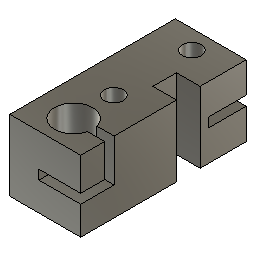
Récupération accélérateur d'origine (Autodesk Fusion 360 archive; units mm, degrees)
design "coulisseau"
Autodesk Fusion 360 part; units mm, degrees
sketch "Esquisse1" plane through (0, 0, 0) normal (0, 0, 1) x (1, 0, 0)
  line L0 (-7.5, 17.5) -> (7.5, 17.5)
  line L1 (7.5, 17.5) -> (7.5, -17.5)
  line L2 (7.5, -17.5) -> (-7.5, -17.5)
  line L3 (-7.5, -17.5) -> (-7.5, 17.5)
  line L4 (0, 50) -> (0, -48.677) construction
  line L5 (-71.4286, 0) -> (60.7143, 0) construction
  circle A0 centre (0, -11.5) radius 4
  circle A1 centre (0, 13.5) radius 2
  circle A2 centre (0, -3) radius 2
  dimension "d1" = 35
  dimension "d2" = 15
  dimension "d3" = 8
  dimension "d4" = 6
  dimension "d7" = 4
  dimension "d8" = 4
  dimension "d15" = 4
  dimension "d16" = 3
  constraint horizontal L0
  constraint vertical L1
  constraint horizontal L2
  constraint vertical L3
  constraint vertical L4
  constraint perpendicular L1 L5
  constraint symmetric L1 L3 L4
  constraint symmetric L0 L2 L5
  constraint coincident L4 A0.centre
  constraint coincident L4 A1.centre
  constraint coincident L4 A2.centre
  measures "d1" distance of L0.end L1.end
  measures "d2" distance of L1.end L2.end
  measures "d3" diameter of A0
  measures "d4" distance of L2 A0.centre
  measures "d7" diameter of A1
  measures "d8" distance of L0 A1.centre
  measures "d15" diameter of A2
  measures "d16" distance of L5 A2.centre
extrude "Extrusion1" add sketch "Esquisse1" along normal blind 15
sketch "Esquisse2" plane through (7.5, 0, 0) normal (1, 0, 0) x (0, 1, 0)
  line L0 (-17.5, 0) -> (17.5, 0)
  line L1 (17.5, 0) -> (17.5, 15)
  line L2 (17.5, 15) -> (-17.5, 15)
  line L3 (-17.5, 15) -> (-17.5, 0)
  line L4 (17.5, 8.5) -> (9.5, 8.5)
  line L5 (9.5, 8.5) -> (9.5, 6.5)
  line L6 (9.5, 6.5) -> (17.5, 6.5)
  line L7 (17.5, 6.5) -> (17.5, 8.5)
  line L8 (-5, 15) -> (-1, 15) construction
  line L9 (-1, 0) -> (-5, 0) construction
  line L10 (11.5, 15) -> (15.5, 15) construction
  line L11 (15.5, 0) -> (11.5, 0) construction
  line L12 (11.5, 15) -> (15.5, 0) construction
  line L13 (-1, 15) -> (-5, 0) construction
  line L14 (13.5, 7.5) -> (-3, 7.5) construction
  line L15 (2.75, 15) -> (7.75, 15)
  line L16 (7.75, 15) -> (7.75, 0)
  line L17 (7.75, 0) -> (2.75, 0)
  line L18 (2.75, 0) -> (2.75, 15)
  line L19 (2.75, 15) -> (7.75, 0) construction
  line L20 (-7.5, 0) -> (-15.5, 0)
  line L21 (-15.5, 15) -> (-7.5, 15)
  line L22 (-7.5, 15) -> (-7.5, 0) construction
  line L23 (-12.4365, 15) -> (-10.4365, 15)
  line L24 (-10.4365, 15) -> (-10.4365, 6.0364)
  line L25 (-10.4365, 6.0364) -> (-12.4365, 6.0364)
  line L26 (-12.4365, 6.0364) -> (-12.4365, 15)
  line L27 (-11.4365, 6.0364) -> (-11.4365, 8) construction
  point P0 (17.5, 7.5)
  point P1 (5.25, 7.5)
  dimension "d10" = 2
  dimension "d11" = 8
  dimension "d17" = 5
  dimension "d20" = 2
  constraint horizontal L4
  constraint vertical L5
  constraint horizontal L6
  constraint vertical L7
  constraint coincident L1 L4.start
  constraint midpoint L7 P0
  constraint coincident L10.start L12.start
  constraint coincident L11.start L12.end
  constraint coincident L8.end L13.start
  constraint coincident L9.end L13.end
  constraint midpoint L13 L14.end
  constraint midpoint L12 L14.start
  constraint midpoint L14 P1
  constraint horizontal L15
  constraint vertical L16
  constraint horizontal L17
  constraint vertical L18
  constraint coincident L0 L16.end
  constraint coincident L2 L15.start
  constraint coincident P1 L19
  constraint coincident L21.end L22.start
  constraint coincident L20.start L22.end
  constraint horizontal L23
  constraint vertical L24
  constraint horizontal L25
  constraint vertical L26
  constraint coincident L21 L23.start
  constraint midpoint L25 L27.start
  constraint perpendicular L25 L27
  measures "d10" distance of L4.start L6.end
  measures "d11" distance of L4.start L4.end
  measures "d17" distance of L15.start L15.end
  measures "d20" distance of L23.start L23.end
extrude "Extrusion2" cut sketch "Esquisse2" against normal up to surface (15 mm away) contours L1 L4 L5 L6 L7
extrude "Extrusion3" cut sketch "Esquisse2" against normal blind 5 contours L0 L2 L15 L16 L17 L18
extrude "Extrusion4" cut sketch "Esquisse2" against normal blind 7 contours L2 L21 L23 L24 L25 L26
sketch "Esquisse3" plane through (0, -17.5, 0) normal (0, -1, 0) x (1, 0, 0)
  line L0 (-7.5, 0) -> (7.5, 0)
  line L1 (7.5, 0) -> (7.5, 15)
  line L2 (7.5, 15) -> (-7.5, 15)
  line L3 (-7.5, 15) -> (-7.5, 0)
  line L4 (4, 0) -> (-4, 0)
  line L5 (3.8888, 15) -> (3.8888, 6.0364)
  line L6 (4, 6.0364) -> (3.856, 6.0364)
  line L7 (3.856, 6.0364) -> (3.856, 15)
  line L8 (-4, 15) -> (3.8888, 15)
  line L9 (7.5, 6.0364) -> (7.5, 15)
  line L10 (7.5, 6.0364) -> (-1.3347, 6.0364)
  line L11 (-1.3347, 6.0364) -> (-1.3347, 8.0364)
  line L12 (-1.3347, 8.0364) -> (7.5, 8.0364)
  line L13 (7.5, 8.0364) -> (7.5, 6.0364)
  dimension "d23" = 2
  constraint horizontal L10
  constraint vertical L11
  constraint horizontal L12
  constraint vertical L13
  constraint coincident L9.start L10.start
  measures "d23" distance of L10.end L11.end
extrude "Extrusion5" cut sketch "Esquisse3" against normal up to surface (7.0635 mm away) contours L1 L5 L6 L9 L10 L12 L13 | L5 L6 L7 L10 L12 | L7 L10 L11 L12

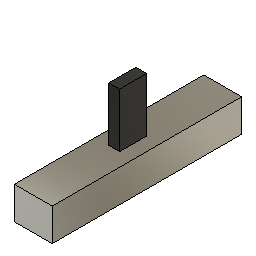
design "potar"
Autodesk Fusion 360 part; units mm, degrees
sketch "Esquisse1" plane through (0, 0, 0) normal (0, 0, 1) x (1, 0, 0)
  line L0 (0, 0) -> (7, 0)
  line L1 (7, 0) -> (7, 35)
  line L2 (7, 35) -> (0, 35)
  line L3 (0, 35) -> (0, 0)
  line L4 (3.5, 37.1833) -> (3.5, -4) construction
  line L5 (2.5, 19.9534) -> (4.5, 19.9534)
  line L6 (4.5, 19.9534) -> (4.5, 14.9534)
  line L7 (4.5, 14.9534) -> (2.5, 14.9534)
  line L8 (2.5, 14.9534) -> (2.5, 19.9534)
  dimension "d1" = 35
  dimension "d2" = 7
  dimension "d3" = 5
  dimension "d4" = 2
  constraint horizontal L0
  constraint vertical L1
  constraint horizontal L2
  constraint vertical L3
  constraint coincident L0.start L3.end
  constraint perpendicular L0 L4
  constraint horizontal L5
  constraint vertical L6
  constraint horizontal L7
  constraint vertical L8
  constraint symmetric L4 L6 L8
  measures "d1" distance of L0.end L1.end
  measures "d2" distance of L0.start L0.end
  measures "d3" distance of L5.end L6.end
  measures "d4" distance of L5.start L5.end
extrude "Extrusion1" add sketch "Esquisse1" against normal blind 6 contours L0 L1 L2 L3 | L5 L6 L7 L8 makes body 1
extrude "Extrusion2" add sketch "Esquisse1" along normal blind 10 separate body contours L5 L6 L7 L8 makes body 2
